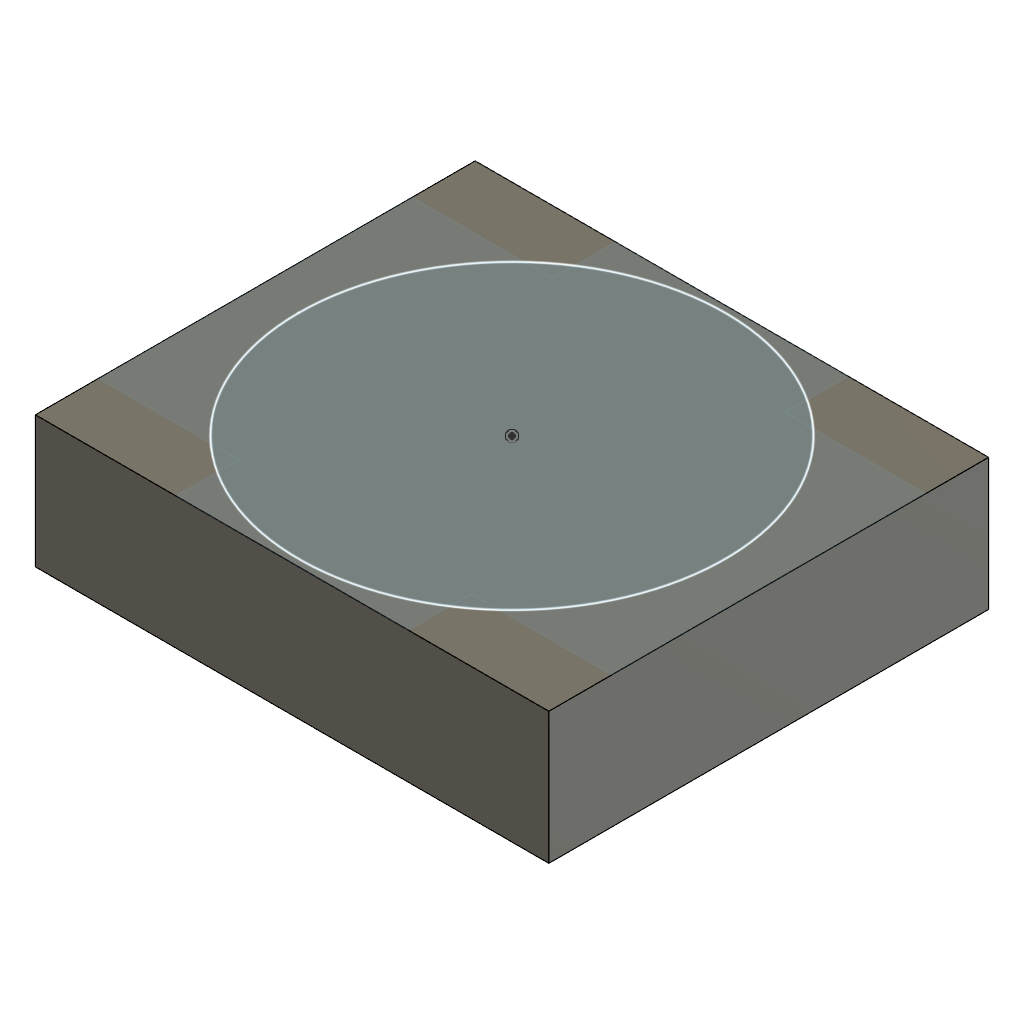
HeadConnectorToServo (Autodesk Fusion 360 design; units mm, degrees)
part number: 2026-07-20-20-42-05-730
Autodesk Fusion 360 part; units mm, degrees
sketch "Sketch1" plane through (0, 0, 0) normal (0, 1, 0) x (1, 0, 0)
  line L0 (12.05, -6.1) -> (-12.05, -6.1)
  line L1 (-12.05, -6.1) -> (-12.05, 6.1)
  line L2 (-12.05, 6.1) -> (12.05, 6.1)
  line L3 (12.05, 6.1) -> (12.05, -6.1)
  line L4 (12.05, -6.1) -> (-12.05, 6.1) construction
  line L5 (-12.05, -6.1) -> (12.05, 6.1) construction
  line L6 (13.05, -8.1) -> (-13.05, -8.1)
  line L7 (-13.05, -8.1) -> (-13.05, 8.1)
  line L8 (-13.05, 8.1) -> (13.05, 8.1)
  line L9 (13.05, 8.1) -> (13.05, -8.1)
  line L10 (13.05, -8.1) -> (-13.05, 8.1) construction
  line L11 (-13.05, -8.1) -> (13.05, 8.1) construction
  dimension "d1" = 24.1
  dimension "d2" = 12.2
  dimension "d3" = 26.1
  dimension "d4" = 16.2
  constraint horizontal L0
  constraint perpendicular L0 L1
  constraint parallel L0 L2
  constraint parallel L1 L3
  constraint coincident L4 origin
  constraint coincident L5 origin
  constraint horizontal L6
  constraint perpendicular L6 L7
  constraint parallel L6 L8
  constraint parallel L7 L9
  constraint coincident L10 origin
  constraint coincident L11 origin
  measures "d1" distance of L1.end L2.end
  measures "d2" distance of L0.end L1.end
  measures "d3" distance of L7.end L8.end
  measures "d4" distance of L6.end L7.end
extrude "Extrude1" add sketch "Sketch1" along normal blind 4 makes body 1
sketch "Sketch2" plane through (0, 4, 0) normal (0, 1, 0) x (-1, 0, 0)
  line L0 (12.05, -6.1) -> (-12.05, -6.1)
  line L1 (-12.05, -6.1) -> (-12.05, 6.1)
  line L2 (-12.05, 6.1) -> (12.05, 6.1)
  line L3 (12.05, 6.1) -> (12.05, -6.1)
  line L4 (-13.05, -8.1) -> (13.05, -8.1)
  line L5 (13.05, -8.1) -> (13.05, 8.1)
  line L6 (13.05, 8.1) -> (-13.05, 8.1)
  line L7 (-13.05, 8.1) -> (-13.05, -8.1)
  line L8 (6, 14.25) -> (-6, 14.25)
  line L9 (-6, 14.25) -> (-6, -14.25)
  line L10 (-6, -14.25) -> (6, -14.25)
  line L11 (6, -14.25) -> (6, 14.25)
  line L12 (6, 14.25) -> (-6, -14.25) construction
  line L13 (-6, 14.25) -> (6, -14.25) construction
  dimension "d7" = 12
  dimension "d8" = 28.5
  constraint horizontal L8
  constraint perpendicular L8 L9
  constraint parallel L8 L10
  constraint parallel L9 L11
  constraint coincident L12 origin
  constraint coincident L13 origin
  measures "d7" distance of L9.end L10.end
  measures "d8" distance of L8.end L9.end
extrude "Extrude2" add sketch "Sketch2" along normal blind 14.4 separate body contours L4 L9 L10 L11 | L6 L8 L9 L11 makes body 2 at (2, 8.8, -14.25) makes body 3 at (-2, 8.8, 8.1)
sketch "Sketch3" plane through (0, 0, -8.1) normal (0, 0, -1) x (-1, 0, 0)
  line L0 (-13.05, 0) -> (13.05, 0)
  line L1 (13.05, 0) -> (13.05, 4)
  line L2 (13.05, 4) -> (-13.05, 4)
  line L3 (-13.05, 4) -> (-13.05, 0)
  line L4 (-6, 4) -> (6, 4)
  line L5 (6, 4) -> (6, 0)
  line L6 (6, 0) -> (-6, 0)
  line L7 (-6, 0) -> (-6, 4)
  constraint horizontal L4
  constraint vertical L5
  constraint horizontal L6
  constraint vertical L7
  constraint coincident L2 L4.start
extrude "Extrude3" add sketch "Sketch3" along normal blind 8 contours L0 L2 L4 L5 L6 L7 bodies 1 2
sketch "Sketch4" plane through (0, 0, 8.1) normal (0, 0, 1) x (1, 0, 0)
  line L0 (-13.05, 0) -> (13.05, 0)
  line L1 (13.05, 0) -> (13.05, 4)
  line L2 (13.05, 4) -> (-13.05, 4)
  line L3 (-13.05, 4) -> (-13.05, 0)
  line L4 (-6, 4) -> (6, 4)
  line L5 (6, 4) -> (6, 0)
  line L6 (6, 0) -> (-6, 0)
  line L7 (-6, 0) -> (-6, 4)
  constraint horizontal L4
  constraint vertical L5
  constraint horizontal L6
  constraint vertical L7
  constraint coincident L2 L4.start
extrude "Extrude4" add sketch "Sketch4" along normal blind 8 contours L0 L2 L4 L5 L6 L7 bodies 1 3
extrude "Extrude5" add 1 faces at (2, 8.8, -14.25) along direction (0, 0, -1) blind 2 on bodies 1 bodies 1
extrude "Extrude6" add 1 faces at (-2, 8.8, 14.25) along direction (0, 0, 1) blind 2 on bodies 1 bodies 1
extrude "Extrude7" cut 1 faces at (2, 8.8, -8.1) along direction (0, 0, -1) blind 5 on bodies 1 bodies 1
extrude "Extrude8" cut 1 faces at (-2, 8.8, 8.1) along direction (0, 0, 1) blind 5 on bodies 1 bodies 1
extrude "Extrude9" add 2 faces at (2, 18.4, -14.15) (-2, 18.4, 14.15) along direction (0, 1, 0) blind 14 on bodies 1 bodies 1
sketch "Sketch5" plane through (0, 0, -13.1) normal (0, 0, 1) x (1, 0, 0)
  line L0 (-6, 4) -> (6, 4)
  line L1 (6, 4) -> (6, 32.4)
  line L2 (6, 32.4) -> (-6, 32.4)
  line L3 (-6, 32.4) -> (-6, 4)
  line L4 (0, 4) -> (0, 27)
  circle A0 centre (0, 24.5) radius 2.5
  constraint midpoint L0 L4.start
  constraint perpendicular L0 L4
  constraint coincident L4.end A0
hole "Hole1" at (0, 24.5, -13.1) direction (0, 0, -1) diameter 5 depth 7 tip angle 180 bodies 1
extrude "Extrude10" add 1 faces at (-2, 2.6667, 16.1) along direction (0, 0, 1) blind 0.1 on bodies 1 bodies 1
extrude "Extrude11" add 1 faces at (-2, 2.6667, 16.2) along direction (0, 0, 1) blind 0.05 on bodies 1 bodies 1
extrude "Extrude12" add 1 faces at (2, 2.6667, -16.1) along direction (0, 0, -1) blind 0.15 on bodies 1 bodies 1
extrude "Extrude13" add 1 faces at (-2, 13.4667, 16.25) along direction (0, 0, 1) blind 5.25 on bodies 1 bodies 1
extrude "Extrude14" add 1 faces at (0, 10, -16.25) along direction (0, 0, -1) blind 5.25 on bodies 1 bodies 1
extrude "Extrude15" cut 1 faces at (-2, 13.4667, 13.1) along direction (0, 0, 1) blind 5.25 on bodies 1 bodies 1
extrude "Extrude16" cut 1 faces at (0, 10, -13.1) along direction (0, 0, -1) blind 5.25 on bodies 1 bodies 1
extrude "Extrude17" add 1 faces at (4.0167, 1.3333, 6.1) along direction (0, 0, -1) blind 0.25 on bodies 1 bodies 1
extrude "Extrude18" add 1 faces at (-4.0167, 1.3333, -6.1) along direction (0, 0, 1) blind 0.25 on bodies 1 bodies 1
extrude "Extrude19" add 1 faces at (13.05, 2.6667, -2.7) along direction (1, 0, 0) blind 0.2 on bodies 1 bodies 1
extrude "Extrude20" cut 1 faces at (12.05, 1.3333, -1.95) along direction (1, 0, 0) blind 0.2 on bodies 1 bodies 1
extrude "Extrude21" add 1 faces at (-13.05, 2.6667, 2.7) along direction (-1, 0, 0) blind 0.2 on bodies 1 bodies 1
extrude "Extrude22" cut 1 faces at (-12.05, 1.3333, 1.95) along direction (-1, 0, 0) blind 0.2 on bodies 1 bodies 1
extrude "Extrude23" add 1 faces at (2, 4, 14.9333) along direction (0, 1, 0) blind 1 on bodies 1 bodies 1
sketch "Sketch6" plane through (12.25, 0, 0) normal (-1, 0, 0) x (0, 0, 1)
  line L0 (-5.85, 5) -> (-5.85, 0)
  line L1 (-5.85, 0) -> (5.85, 0)
  line L2 (5.85, 0) -> (5.85, 5)
  line L3 (5.85, 5) -> (-5.85, 5)
  line L4 (-5.85, 5) -> (5.85, 5)
  line L5 (5.85, 5) -> (5.85, 4)
  line L6 (5.85, 4) -> (-5.85, 4)
  line L7 (-5.85, 4) -> (-5.85, 5)
  dimension "d56" = 1
  constraint horizontal L4
  constraint vertical L5
  constraint horizontal L6
  constraint vertical L7
  constraint coincident L0.start L3.end
  measures "d56" distance of L0.start L6.end
extrude "Extrude24" add sketch "Sketch6" along normal blind 2 contours L0 L2 L3 L4 L5 L6 L7 bodies 1
sketch "Sketch7" plane through (-12.25, 0, 0) normal (1, 0, 0) x (0, 0, -1)
  line L0 (5.85, 0) -> (5.85, 5)
  line L1 (5.85, 5) -> (-5.85, 5)
  line L2 (-5.85, 5) -> (-5.85, 0)
  line L3 (-5.85, 0) -> (5.85, 0)
  line L4 (-5.85, 5) -> (5.85, 5)
  line L5 (5.85, 5) -> (5.85, 4)
  line L6 (5.85, 4) -> (-5.85, 4)
  line L7 (-5.85, 4) -> (-5.85, 5)
  dimension "d59" = 1
  constraint horizontal L4
  constraint vertical L5
  constraint horizontal L6
  constraint vertical L7
  constraint coincident L1.end L2.start
  measures "d59" distance of L1.end L6.end
extrude "Extrude25" add sketch "Sketch7" along normal blind 2 contours L0 L1 L2 L4 L5 L6 L7 bodies 1
extrude "Extrude26" cut 1 faces at (-2, 32.4, 19.4) along direction (0, -1, 0) blind 27 on bodies 1 bodies 1
extrude "Extrude27" cut 1 faces at (2, 32.4, -19.4) along direction (0, -1, 0) blind 36 on bodies 1 bodies 1
extrude "Extrude28" cut 1 faces at (-2, 5.4, 19.4) along direction (0, -1, 0) blind 8 on bodies 1 bodies 1
extrude "Extrude29" cut 1 faces at (2, 3.3333, -18.35) along direction (0, 0, 1) blind 7 on bodies 1 bodies 1
extrude "Extrude30" cut 1 faces at (-2, 3.3333, 18.35) along direction (0, 0, -1) blind 7 on bodies 1 bodies 1
extrude "Extrude31" cut 1 faces at (-10.25, 4.6667, 1.95) along direction (1, 0, 0) blind 21 on bodies 1 bodies 1
extrude "Extrude32" add 1 faces at (-10.25, 4.6667, 1.95) along direction (1, 0, 0) blind 21 on bodies 1 bodies 1
extrude "Extrude33" add 1 faces at (2, 0, 9.1833) along direction (0, -1, 0) blind 1.8 on bodies 1 bodies 1
sketch "Sketch8" plane through (0, 5, 0) normal (0, 1, 0) x (-1, 0, 0)
  line L0 (6, 11.35) -> (-6, 11.35)
  line L1 (-6, 11.35) -> (-6, 8.1)
  line L2 (-6, 8.1) -> (-13.25, 8.1)
  line L3 (-13.25, 8.1) -> (-13.25, -8.1)
  line L4 (-13.25, -8.1) -> (-6, -8.1)
  line L5 (-6, -8.1) -> (-6, -11.35)
  line L6 (-6, -11.35) -> (6, -11.35)
  line L7 (6, -11.35) -> (6, -8.1)
  line L8 (6, -8.1) -> (13.25, -8.1)
  line L9 (13.25, -8.1) -> (13.25, 8.1)
  line L10 (13.25, 8.1) -> (6, 8.1)
  line L11 (6, 8.1) -> (6, 11.35)
  circle A0 centre (0, 0) radius 11
  dimension "d78" = 22
  constraint coincident A0.centre origin
  measures "d78" diameter of A0
extrude "Extrude34" add 1 faces at (-10.8333, 2.4, 8.1) along direction (0, 0, 1) blind 3.25 on bodies 1 bodies 1
extrude "Extrude35" add 1 faces at (10.8333, 2.4, 8.1) along direction (0, 0, 1) blind 3.25 on bodies 1 bodies 1
extrude "Extrude36" add 2 faces at (10.8333, 2.4, -8.1) (-10.8333, 2.4, -8.1) along direction (0, 0, -1) blind 3.25 on bodies 1 bodies 1
extrude "Extrude37" add 1 faces at (2, 0.4667, -11.35) along direction (0, 0, -1) blind 2 on bodies 1 bodies 1
extrude "Extrude38" add 1 faces at (-2, 0.4667, 11.35) along direction (0, 0, 1) blind 2 on bodies 1 bodies 1
sketch "Sketch9" plane through (0, 5, 0) normal (0, 1, 0) x (-1, 0, 0)
  circle A0 centre (0, 0) radius 11
  dimension "d89" = 22
  constraint coincident A0.centre origin
  measures "d89" diameter of A0
sketch "Sketch10" plane through (0, 5, 0) normal (0, 1, 0) x (-1, 0, 0)
  circle A0 centre (0, 0) radius 12
  dimension "d90" = 24
  constraint coincident A0.centre origin
  measures "d90" diameter of A0
extrude "Extrude39" add sketch "Sketch10" along normal blind 7 thin wall 1 inside bodies 1
extrude "Extrude40" cut 1 faces at (-11.622, 12, -0.5962) along direction (0, -1, 0) blind 7 on bodies 1 bodies 1
extrude "Extrude41" cut 1 faces at (2, 0.4667, -13.35) along direction (0, 0, 1) blind 2 on bodies 1 bodies 1
extrude "Extrude42" cut 1 faces at (-2, 0.4667, 13.35) along direction (0, 0, -1) blind 2 on bodies 1 bodies 1
